111102_P01_BASE-BAND-TUBE-SIDE-RH_CAD (Autodesk Fusion 360 design; units mm, degrees)
description: BASE - BAND TUBE - SIDE - RH | Viền chân nhôm 100x40 - cạnh phải | part we make | rev P01 | DRAFT
part number: 111102
Autodesk Fusion 360 part; units mm, degrees
note: some values were not read from the file. Set by a fixed rule: the direction of a hole.
ref_plane "WorkPlane1" through (0, 0, 10) normal (0, 0, 1) x (1, 0, 0)
sketch "PLAN - SIDE RH - OUTLINE" plane through (0, 0, 10) normal (0, 0, 1) x (1, 0, 0)
  line L0 (1250, 850) -> (1250, -672)
  line L1 (1250, -672) -> (1210, -654.1721)
  line L2 (1210, -654.1721) -> (1210, 850)
  line L3 (1210, 850) -> (1250, 850)
  dimension "d169" = 1250
  dimension "d170" = 1210
  dimension "d171" = 672
  dimension "d172" = 654.1721
  dimension "d173" = 850
  constraint vertical L0
  constraint vertical L2
  constraint horizontal L3
  measures "d169" horizontal distance of origin L0.start
  measures "d170" horizontal distance of origin L1.end
  measures "d171" vertical distance of origin L0.end
  measures "d172" vertical distance of origin L1.end
  measures "d173" vertical distance of origin L2.end
extrude "EXTRUDE - SIDE RH - TUBE OUTSIDE" add sketch "PLAN - SIDE RH - OUTLINE" along normal blind 100
sketch "PLAN - SIDE RH - BORE" plane through (0, 0, 10) normal (0, 0, 1) x (1, 0, 0)
  line L0 (1211.5, -692) -> (1248.5, -692)
  line L1 (1248.5, -692) -> (1248.5, 870)
  line L2 (1248.5, 870) -> (1211.5, 870)
  line L3 (1211.5, 870) -> (1211.5, -692)
  dimension "d176" = 1248.5
  dimension "d177" = 1211.5
  dimension "d178" = 692
  dimension "d179" = 870
  constraint vertical L1
  constraint vertical L3
  constraint horizontal L0
  constraint horizontal L2
  measures "d176" horizontal distance of origin L0.end
  measures "d177" horizontal distance of origin L2.end
  measures "d178" vertical distance of origin L0.start
  measures "d179" vertical distance of origin L1.end
extrude "CUT - SIDE RH - BORE, WALL band_wall" cut sketch "PLAN - SIDE RH - BORE" along normal blind 97 from surface at 1.5
ref_plane "WorkPlane2" through (1210, 0, 0) normal (1, 0, 0) x (0, 1, 0)
sketch "HOLE POSITION - BACK KEY HOOK STUD BOLTS - BR (111211, D-129)" plane through (1210, 0, 0) normal (1, 0, 0) x (0, 0, -1)
  point P0 (-37.5, 830)
  dimension "d185" = 830
  dimension "d186" = 37.5
  measures "d185" vertical distance of origin P0
  measures "d186" horizontal distance of origin P0
hole "HOLE - BACK KEY HOOK STUD BOLTS - BR (111211, D-129)" at (1210, 830, 37.5) direction (1, 0, 0) diameter 7 depth 1.5 tip angle 118
pattern_linear "PATTERN - BACK KEY HOOK STUD BOLTS - BR (111211, D-129)" count 2 spacing 34 along (0, 0, 1) of "HOLE - BACK KEY HOOK STUD BOLTS - BR (111211, D-129)"
sketch "HOLE POSITION - BACK KEY FIXING - BR (111211, D-129)" plane through (0, 0, 10) normal (0, 0, 1) x (1, 0, 0)
  point P0 (1231, 823)
  dimension "d194" = 1231
  dimension "d195" = 823
  measures "d194" horizontal distance of origin P0
  measures "d195" vertical distance of origin P0
hole "HOLE - BACK KEY FIXING - BR (111211, D-129)" at (1231, 823, 10) direction (0, 0, 1) diameter 7 depth 1.5 tip angle 118
pattern_linear "PATTERN - BACK KEY FIXING - BR (111211, D-129)" count 2 spacing 14 along (0, 1, 0) of "HOLE - BACK KEY FIXING - BR (111211, D-129)"
ref_plane "WorkPlane3" through (0, 0, 110) normal (0, 0, 1) x (1, 0, 0)
sketch "HOLE POSITION - J-BASE-01 RIVNUT - R1" plane through (0, 0, 110) normal (0, 0, 1) x (1, 0, 0)
  point P0 (1224, -422.74)
  dimension "d205" = 1224
  dimension "d206" = 422.74
  measures "d205" horizontal distance of origin P0
  measures "d206" vertical distance of origin P0
hole "HOLE - J-BASE-01 RIVNUT - R1" at (1224, -422.74, 110) direction (0, 0, -1) diameter 9.53 depth 1.5 tip angle 118
pattern_linear "PATTERN - J-BASE-01 RIVNUT - R1" count 4 spacing 350.9133 along (0, 1, 0) of "HOLE - J-BASE-01 RIVNUT - R1"
sketch "HOLE POSITION - SPIGOT RIVNUT - R1" plane through (0, 0, 110) normal (0, 0, 1) x (1, 0, 0)
  point P0 (1224, -542.74)
  dimension "d214" = 1224
  dimension "d215" = 542.74
  measures "d214" horizontal distance of origin P0
  measures "d215" vertical distance of origin P0
hole "HOLE - SPIGOT RIVNUT - R1" at (1224, -542.74, 110) direction (0, 0, -1) diameter 9.53 depth 1.5 tip angle 118
pattern_linear "PATTERN - SPIGOT RIVNUT - R1" count 2 spacing 1292.74 along (0, 1, 0) of "HOLE - SPIGOT RIVNUT - R1"
sketch "HOLE POSITION - CORNER KEY FIXING - FR (111213)" plane through (0, 0, 10) normal (0, 0, 1) x (1, 0, 0)
  point P0 (1223, -643.5861)
  dimension "d223" = 1223
  dimension "d224" = 643.5861
  measures "d223" horizontal distance of origin P0
  measures "d224" vertical distance of origin P0
hole "HOLE - CORNER KEY FIXING - FR (111213)" at (1223, -643.5861, 10) direction (0, 0, 1) diameter 7 depth 1.5 tip angle 118
pattern_linear "PATTERN - CORNER KEY FIXING - FR (111213)" count 2 spacing 14 along (1, 0, 0) of "HOLE - CORNER KEY FIXING - FR (111213)"
sketch "HOLE POSITION - GLIDE KEY ACCESS - SIDE RH" plane through (0, 0, 110) normal (0, 0, 1) x (1, 0, 0)
  point P0 (1230, -597)
  dimension "d232" = 1230
  dimension "d233" = 597
  measures "d232" horizontal distance of origin P0
  measures "d233" vertical distance of origin P0
hole "HOLE - GLIDE KEY ACCESS - SIDE RH" at (1230, -597, 110) direction (0, 0, -1) diameter 8 depth 1.5 tip angle 118
pattern_linear "PATTERN - GLIDE KEY ACCESS - SIDE RH" count 2 spacing 1297 along (0, 1, 0) of "HOLE - GLIDE KEY ACCESS - SIDE RH"
sketch "HOLE POSITION - GLIDE NUT - SIDE RH" plane through (0, 0, 10) normal (0, 0, 1) x (1, 0, 0)
  point P0 (1230, -597)
  dimension "d241" = 1230
  dimension "d242" = 597
  measures "d241" horizontal distance of origin P0
  measures "d242" vertical distance of origin P0
hole "HOLE - GLIDE NUT - SIDE RH" at (1230, -597, 10) direction (0, 0, 1) diameter 13 depth 1.5 tip angle 118
pattern_linear "PATTERN - GLIDE NUT - SIDE RH" count 2 spacing 1297 along (0, 1, 0) of "HOLE - GLIDE NUT - SIDE RH"
equation "pod_w = 2500 mm" comment "SKELETON DECIDED: D-01; conventions s4 (X = +-1250)"
equation "pod_d = 1700 mm" comment "SKELETON DECIDED: D-01; conventions s4 (Y = +-850)"
equation "pod_h = 2400 mm" comment "SKELETON DECIDED: D-21 (room floor to roof skin top)"
equation "glide_h = 10 mm" comment "SKELETON ASSUMPTION: layout study inputs.py glide_h"
equation "band_h = 100 mm" comment "SKELETON SOURCE: layout study B1 list B-BAND 100x40; inputs.py base_h"
equation "band_t = 40 mm" comment "SKELETON SOURCE: layout study B1 list B-BAND 100x40"
equation "skin_t = 3 mm" comment "SKELETON DECIDED: ACP skin, walls and ceiling (D-16; PM ruling 2026-10-31 on outer_t)"
equation "bond_t = 3 mm" comment "SKELETON DECIDED: bond line between the ACP and the frame (PM ruling 2026-10-31 on outer_t)"
equation "frame_t = 40 mm" comment "SKELETON DECIDED: aluminium frame tube depth, walls and ceiling (PM ruling 2026-10-31 on outer_t)"
equation "outer_t = skin_t + bond_t + frame_t" comment "SKELETON DECIDED: PM ruling 2026-10-31: ACP 3 + bond line 3 + frame 40, walls and ceiling (was 43)"
equation "cav_gap = 4 mm" comment "SKELETON DECIDED: D-16, D-42: the gap between the outer panel and the lining cassette in the wall and ceiling stack"
equation "cass_t = 34 mm" comment "SKELETON SOURCE: layout study B1 final list L-CASS 34 (tray + 25 gap + felt 9)"
equation "stack_t = outer_t + cav_gap + cass_t" comment "SKELETON CALCULATION: D-16, D-42 stack, walls and ceiling: outer panel + cavity gap + cassette (PM ruling 2026-10-31 on outer_t)"
equation "wall_depth = 1495 mm" comment "SKELETON DECIDED: PM ruling pass C: side walls start at the decor back plate (Y -645), as v1 (1496)"
equation "lin_gap = 4 mm" comment "SKELETON ASSUMPTION: PM ruling pass C: gap above the upper side linings so they stay floating (= the 4 mm stack gap)"
equation "seam_gap = 2.26 mm" comment "SKELETON DECIDED: PM ruling 2026-10-31 (Mechanical Checker F-001, F-005): the Joints Engineer's 2.26 mm at all nine site seam types, set by a metal stop (1.5 stop washer + 0.76 rivnut head; joints register section 2.8)"
equation "mat_t = 0 mm" comment "SKELETON DECIDED: D-132 (PM ruling 2026-11-01): no floor, so no floor mat (was 3, D-72)"
equation "floor_t = 0 mm" comment "SKELETON DECIDED: D-132 (PM ruling 2026-11-01): no floor; people stand on the room floor (was 9)"
equation "thresh_h = 0 mm" comment "SKELETON DECIDED: D-132 (PM ruling 2026-11-01): no threshold, no step at the door; the door's drop seal closes on the room floor (was 13)"
equation "decor_d = 205 mm" comment "SKELETON SOURCE: v1 geometry per the PM ruling on D-39 (as v1; the drawings win): v1 decor-frame drawing frames 191 (left) and 197 (right) deep plus ACP and back plate = the v1 STEP shell, Y -850 to -645 = 205. D-39 and the B1 list say 230-235 (v1 BOM); see BUILD-RECORD-P02"
equation "dl_w = 278 mm" comment "SKELETON SOURCE: B1 list F-DL 278 (v1 BOM DL)"
equation "dr_w = 1016 mm" comment "SKELETON SOURCE: B1 list F-DR 1016 (v1 STEP solid 78)"
equation "dt_w = 1697 mm" comment "SKELETON SOURCE: B1 list F-DT 1697 (v1 BOM DT)"
equation "dt_h = 280 mm" comment "SKELETON SOURCE: B1 list F-DT 280"
equation "door_w = 1176 mm" comment "SKELETON DECIDED: D-46"
equation "door_h = 2011 mm" comment "SKELETON SOURCE: B1 list F-GLASS-DOOR 2011; v1 STEP solid 238"
equation "glass_t = 8.76 mm" comment "SKELETON DECIDED: D-46 (4+4 laminate)"
equation "glass_y = 699 mm" comment "SKELETON SOURCE: v1 STEP solid 238 centre Y = -699 (layout study data)"
equation "kick_d = 20 mm" comment "SKELETON ASSUMPTION: kick strip envelope depth (D-40 gives the height only)"
equation "kick_gap = 7 mm" comment "SKELETON SOURCE: FRONT door unit: 7 mm running gap under the kick strip for the drop seal (Mechanical Checker F-002 on P03); since D-132 the PM puts the kick strip's bottom on the band's bottom line, glide_h, so the skeleton's kick envelope no longer uses it"
equation "fr_dz = 17 mm" comment "SKELETON CALCULATION: v1 front top 2417 (v2 frame) - pod_h 2400"
equation "door_xl = 289 mm" comment "SKELETON SOURCE: V1-FRONT-FACETS: door left edge X -961 = -1250 + 289"
equation "door_xbr = 1464 mm" comment "SKELETON SOURCE: V1-FRONT-FACETS: door bottom-right X 214"
equation "door_xtr = 1182 mm" comment "SKELETON SOURCE: V1-FRONT-FACETS: door top-right X -68"
equation "door_zb = 122 mm - fr_dz" comment "SKELETON SOURCE: V1-FRONT-FACETS: door bottom Z 122"
equation "door_zt = 2133 mm - fr_dz" comment "SKELETON SOURCE: V1-FRONT-FACETS: door top Z 2133"
equation "glass_gap = 4 mm" comment "SKELETON DECIDED: PM ruling 2026-10-31 on Mechanical Checker F-014: the fixed glass's free edge runs parallel to the door's slanted edge, 4.0 mm away (FRONT's glass in PR #28 is the reference)"
equation "fix_xbr = 302 mm" comment "SKELETON SOURCE: V1-FRONT-FACETS: fixed glass bottom-right X 948 = 1250 - 302"
equation "fix_xk = 501 mm" comment "SKELETON SOURCE: V1-FRONT-FACETS: fixed glass knee X 749 = 1250 - 501"
equation "fix_zk = 1538 mm - fr_dz" comment "SKELETON SOURCE: V1-FRONT-FACETS: fixed glass knee Z 1538"
equation "fix_xtr = 1480 mm" comment "SKELETON SOURCE: V1-FRONT-FACETS: fixed glass top-right X 230 = -1250 + 1480"
equation "fix_zb = 119 mm - fr_dz" comment "SKELETON SOURCE: V1-FRONT-FACETS: fixed glass bottom Z 119"
equation "fix_zt = 2136 mm - fr_dz" comment "SKELETON SOURCE: V1-FRONT-FACETS: fixed glass top Z 2136"
equation "dt_zb = 2137 mm - fr_dz" comment "SKELETON SOURCE: V1-FRONT-FACETS: DT and DR edge above the glass Z 2137"
equation "ch_zlo = 2217 mm - fr_dz" comment "SKELETON SOURCE: V1-FRONT-FACETS: top chamfer front edge Z 2217 at Y -848"
equation "ch_yb = 672 mm" comment "SKELETON SOURCE: V1-FRONT-FACETS: top chamfer back edge Y -672"
equation "dl_x2 = 92 mm" comment "SKELETON SOURCE: V1-FRONT-FACETS: DL facet knee X -1158 = -1250 + 92"
equation "dl_y2 = 752 mm" comment "SKELETON SOURCE: V1-FRONT-FACETS: DL facet knee Y -752"
equation "dl_x3 = 271 mm" comment "SKELETON SOURCE: V1-FRONT-FACETS: DL front corner X -979"
equation "dl_y3 = 844 mm" comment "SKELETON SOURCE: V1-FRONT-FACETS: DL front corner Y -844"
equation "dl_y1 = 670 mm" comment "SKELETON SOURCE: V1-FRONT-FACETS: DL outer facet start Y -670"
equation "dl_zo = 2414 mm - fr_dz" comment "SKELETON SOURCE: V1-FRONT-FACETS: DL top at the outer corner Z 2414"
equation "dt_x2 = 281 mm" comment "SKELETON SOURCE: V1-FRONT-FACETS: DT lower facet left X -969 = -1250 + 281"
equation "dt_y2 = 767 mm" comment "SKELETON SOURCE: V1-FRONT-FACETS: DT lower facet left Y -767"
equation "dt_y3 = 753 mm" comment "SKELETON SOURCE: V1-FRONT-FACETS: DT lower facet outer Y -753 at X -1154"
equation "dr_xc = 198 mm" comment "SKELETON SOURCE: V1-FRONT-FACETS: DR corner facet front X 1052 = 1250 - 198"
equation "dt_xr = 1699 mm" comment "SKELETON SOURCE: V1-FRONT-FACETS: DT/DR joint at the top, X 449 = -1250 + 1699 (PM ruling pass C)"
equation "dr_yc = 672 mm" comment "SKELETON SOURCE: V1-FRONT-FACETS: DR corner facet back Y -672"
equation "fix_xbl = door_xbr + ( door_zb - fix_zb ) * ( door_xbr - door_xtr ) / ( door_zt - door_zb ) + glass_gap * sqrt(( door_xbr - door_xtr ) * ( door_xbr - door_xtr ) + ( door_zt - door_zb ) * ( door_zt - door_zb )) / ( door_zt - door_zb )" comment "SKELETON CALCULATION: F-014: fixed glass bottom-left, on the line glass_gap from the door's slanted edge (was v1's 1468)"
equation "fix_xtl = door_xbr + ( door_zb - fix_zt ) * ( door_xbr - door_xtr ) / ( door_zt - door_zb ) + glass_gap * sqrt(( door_xbr - door_xtr ) * ( door_xbr - door_xtr ) + ( door_zt - door_zb ) * ( door_zt - door_zb )) / ( door_zt - door_zb )" comment "SKELETON CALCULATION: F-014: fixed glass top-left, on the same line (was v1's 1184)"
equation "floor_top = mat_t + floor_t" comment "SKELETON CALCULATION: the floor top: Z 0, the room floor itself (D-132: no floor; was Z 12)"
equation "wall_z0 = glide_h + band_h" comment "SKELETON CALCULATION: base band top: glides + band"
equation "panel_z0 = wall_z0 + seam_gap" comment "SKELETON CALCULATION: walls stand one seam_gap above the band top (joints register 2.8, IF-01)"
equation "wall_h = pod_h - wall_z0" comment "SKELETON CALCULATION: 2290 = layout study v2_model wall_h"
equation "side_h = ( wall_h - 2 * seam_gap ) / 2" comment "SKELETON CALCULATION: D-23: 2 sheets per side wall; the gap on the band and the horizontal seam (joints register 2.8)"
equation "side_l = wall_depth - seam_gap" comment "SKELETON CALCULATION: side panel length along Y: the seam_gap at the decor's back plate (joints register 2.8, IF-07)"
equation "back_oh = pod_h - outer_t - seam_gap - panel_z0" comment "SKELETON CALCULATION: PM ruling 2026-10-31 (pass D, F-004): the back outer frames run up to the ceiling frame (pod_h - outer_t), less the seam_gap under it, closing the slot at the back top edge"
equation "back_ph = ( back_oh - seam_gap ) / 2" comment "SKELETON CALCULATION: D-23: 4 sheets on the back, two equal rows with one seam_gap between them (joints register 2.8); the lower back linings match the lower row, as on the side walls"
equation "half_pw = ( pod_w - 2 * outer_t - 3 * seam_gap ) / 2" comment "SKELETON CALCULATION: SKIN width of each back and ceiling panel: two skins and three seam_gap seams between the side frames (F-001, joints register 2.8)"
equation "close_gap = 5.5 mm" comment "SKELETON DECIDED: PM ruling 2026-10-31 (joints register, F-011/F-012): frame gap at the closing seams B1-B2, B3-B4 and C1-C2, which have no hard stop (slotted holes, thicker gasket)"
equation "half_fw = ( pod_w - 2 * outer_t - 2 * seam_gap - close_gap ) / 2" comment "SKELETON CALCULATION: FRAME width of each back and ceiling panel: the skins overhang their frames by half_pw - half_fw at the closing seam (PM ruling 2026-10-31)"
equation "inner_w = pod_w - 2 * stack_t" comment "SKELETON CALCULATION: inside width between the side linings"
equation "bolt_edge_inset = 220 mm" comment "SKELETON DECIDED: PM ruling 2026-10-31: on every bolted edge the end bolts sit this far in from each panel end (the FRAME end, where the bolts go), the rest evenly spaced"
equation "spigot_inset = 100 mm" comment "SKELETON DECIDED: PM ruling 2026-10-31: locating spigots this far in from each panel end (round hole at one end, slot at the other)"
equation "base_bolt_edge = bolt_edge_inset" comment "SKELETON DECIDED: J-BASE-01 wall to band: the edge rule (kept by this name for parts already linked)"
equation "n_base_bolt = 4" comment "SKELETON DECIDED: PM ruling 2026-10-31, J-BASE-01: bolts per panel along the band, evenly spaced"
equation "base_spigot_inset = spigot_inset" comment "SKELETON DECIDED: J-BASE-01: the spigot rule (kept by this name for parts already linked)"
equation "base_side_y0 = pod_d / 2 - wall_depth + seam_gap" comment "SKELETON CALCULATION: J-BASE-01: side bolt lines start at the side panel's front end (first bolt base_bolt_edge further on)"
equation "side_base_pitch = ( side_l - 2 * base_bolt_edge ) / ( n_base_bolt - 1 )" comment "SKELETON CALCULATION: J-BASE-01 bolt pitch along a side panel"
equation "base_back_x0 = pod_w / 2 - outer_t - seam_gap" comment "SKELETON CALCULATION: J-BASE-01: back bolt lines start at each back FRAME's outer end, X -/+ this (first bolt base_bolt_edge further in)"
equation "back_base_pitch = ( half_fw - 2 * base_bolt_edge ) / ( n_base_bolt - 1 )" comment "SKELETON DECIDED: PM ruling 2026-10-31 (Reviewer 5 P2 on #58): J-BASE-01 pitch along a back panel, measured on the FRAME (half_fw), where the bolts go; 'panel end' means the frame end"
equation "ceil_bolt_z = pod_h - outer_t + frame_t / 2" comment "SKELETON DECIDED: PM ruling 2026-10-31, J-CEIL-01 wall to ceiling: the bolt line on the ceiling frame's centre (Z 2374)"
equation "n_ceil_side_bolt = 4" comment "SKELETON DECIDED: PM ruling 2026-10-31, J-CEIL-01: bolts along each side wall top"
equation "n_ceil_back_bolt = 4" comment "SKELETON DECIDED: PM ruling 2026-10-31, J-CEIL-01: bolts along each back panel top, like the base (pitch about 253, every edge 350 or less; joints register: 82 bolts in all)"
equation "ceil_side_y0 = pod_d / 2 - wall_depth" comment "SKELETON DECIDED: PM ruling 2026-10-31 (joints register): J-CEIL-01 side bolt lines start at Y -645, measured along the ceiling (first bolt bolt_edge_inset further on)"
equation "ceil_side_pitch = ( wall_depth - 2 * bolt_edge_inset ) / ( n_ceil_side_bolt - 1 )" comment "SKELETON DECIDED: PM ruling 2026-10-31 (joints register): J-CEIL-01 pitch along a side wall top, over the ceiling's length (was over the side panel's)"
equation "ceil_back_x0 = pod_w / 2 - outer_t - seam_gap" comment "SKELETON DECIDED: PM ruling 2026-10-31 (joints register): J-CEIL-01 back bolt lines start at each back frame's outer end, X -/+ this"
equation "ceil_back_pitch = ( half_fw - 2 * bolt_edge_inset ) / ( n_ceil_back_bolt - 1 )" comment "SKELETON DECIDED: PM ruling 2026-10-31 (joints register): J-CEIL-01 pitch along a back panel top, on the frame (half_fw)"
equation "band_wall = 1.5 mm" comment "BASE CONFIRMED: PM ruling 2026-10-31 (BASE group): 100 x 40 x 1.5 base band (was 2.0), with a doubler at each glide; rivnut coupon in 1.5 mm added to the rivnut test"
equation "band_finish = 'Black anodised, matte, 20 um (class AA20, EN ISO 7599)'" comment "BASE CONFIRMED: PM ruling 2026-10-31 (BASE group): every base band piece and the door's kick strip"
equation "cap_t = 2 mm" comment "BASE SOURCE: the side band's back-end cap 118003: flat, inside the tube's end and flush with the back face Y = pod_d/2, no deeper than 2, as the back corner key sits 2.5 from the end (D-129, joints register J-BASE-02); product HOLD"
equation "jb_x = outer_t - frame_t / 2" comment "BASE CALCULATION: J-BASE-01 bolt line: centre of the wall's bottom tube, 26 in from the pod's outer face (joints register 3.4: X -1224, Y +824)"
equation "rn_hole = 9.53 mm" comment "BASE SOURCE: Sherex CAH2-610-4.2 M6 rivet nut, steel, zinc plated (joints register H-03, D-131): hole 9.53 +0.10/0, as the aluminium part's it replaced (unverified for the steel part, HOLD-04)"
equation "rn_flange = 12.96 mm" comment "BASE SOURCE: CAH2-610-4.2 head diameter 12.96 (joints register H-03)"
equation "rn_inst = 10.16 mm" comment "BASE SOURCE: CAH2-610-4.2 installed length, at most 10.16 (joints register H-03, maker data)"
equation "rn_head_t = 0.76 mm" comment "BASE SOURCE: CAH2-610-4.2 head height 0.76 +-0.08 (joints register H-03, maker data)"
equation "sw_hole = 10.5 mm" comment "BASE SOURCE: stop washer bore (joints register H-08, PROPOSED)"
equation "sw_d = 20 mm" comment "BASE SOURCE: stop washer outside diameter (joints register H-08, PROPOSED)"
equation "sw_t = 1.5 mm" comment "BASE SOURCE: stop washer, under each bolt rivnut's head: washer 1.5 + head 0.76 = seam_gap 2.26, so the walls stand at panel_z0 (D-64)"
equation "jb_n = n_base_bolt" comment "BASE CONFIRMED: skeleton n_base_bolt (D-75, joints register R-J13): 4 bolts per wall panel on the band"
equation "jb_e = base_bolt_edge" comment "BASE CONFIRMED: skeleton base_bolt_edge (D-75, R-J13): end bolts 220 in from each panel FRAME end, evenly spaced (PM ruling: measured on the frame, not the skin)"
equation "sp_e = base_spigot_inset" comment "BASE CONFIRMED: skeleton base_spigot_inset (D-75, R-J13): spigots 100 in from each panel frame end"
equation "sp_dia = 8 mm" comment "BASE SOURCE: locating spigot, stainless, M6 thread (joints register H-05, PROPOSED sizes)"
equation "sp_proud = 8 mm" comment "BASE SOURCE: spigot stands 8 proud of the band top (joints register H-05, PROPOSED)"
equation "sp_ch = 1 mm" comment "BASE ASSUMPTION: lead-in chamfer on the spigot top"
equation "sp_stud = 8 mm" comment "BASE ASSUMPTION: spigot's M6 stud into its rivnut, with threadlocker"
equation "gl_n_side = 2" comment "BASE CALCULATION: glides per side band: span about 1.3 m, sag under 0.5 mm (see feature rationale)"
equation "gl_n_back = 3" comment "BASE CALCULATION: glides on the back band: 2 spans of 1060 (see feature rationale)"
equation "gl_e_f = 75 mm" comment "BASE CALCULATION: front glide of a side band, behind the band's outer front corner (Y = -dl_y1): its doubler (26 each way) stays 15 behind the front corner key's back face (Y -636.03) and out of the keyed end's last 30 mm, which the joints register asks BASE to keep clear (PR #99, J-BASE-02)"
equation "gl_e_b = 150 mm" comment "BASE ASSUMPTION: back glide of a side band from the back face"
equation "gl_e_bb = 150 mm" comment "BASE ASSUMPTION: end glides of the back band from its ends"
equation "gl_key_hole = 8 mm" comment "BASE ASSUMPTION: hole in the band top for the 5 mm hex key that turns the glide (5.77 across corners, so 1.1 clear each side; levelled before the walls go on). On the band's centre line it spans 16 to 24 from the outer face, inboard of the PORON strip that runs beside the washer line on its outer side (8 to 16, joints register FR-11)"
equation "gl_dx = 0 mm" comment "BASE CONFIRMED: PM ruling 2026-10-31 (BASE group): the doubler's hole centred across its 36 mm width, so the glide stands on the band's centre line"
equation "gl_nut_hole = 13 mm" comment "BASE ASSUMPTION: hole in the band bottom for an M10 rivet nut that carries the glide; nut product HOLD"
equation "gl_pad = 36 mm" comment "BASE ASSUMPTION: glide pad diameter (envelope, HOLD); stays inside the band's 40 mm width"
equation "gl_stem = 10 mm" comment "BASE ASSUMPTION: glide stem M10 (envelope, HOLD)"
equation "gl_nut_t = 2 mm" comment "BASE ASSUMPTION: M10 rivet nut head under the band, between the band and the glide pad (HOLD)"
equation "gl_min = 8.5 mm" comment "BASE SOURCE: lowest glide setting: the corner keys' button heads hang 3.3 under the band and nothing may come within 5 of the floor (PM ruling on F-018; joints register PR #99 via the Lead, 2026-11-01)"
equation "gl_base_min = gl_min - gl_nut_t" comment "BASE CALCULATION: the glide's base must stand this tall (6.5), so that screwed fully home against the M10 rivnut's head it holds the band at gl_min: a hard stop (glide spec, HOLD)"
equation "gd_l = 54 mm" comment "BASE CONFIRMED: PM ruling 2026-10-31 (BASE group, the Checker's edge rule): glide doubler at least 52 long, so its ends are 2 hole diameters (26) from the hole; 54 gives 27, clear of that line"
equation "gd_w = band_t - 2 * band_wall - 1 mm" comment "BASE CALCULATION: glide doubler width: the band's bore less 1 mm, so it bears on the bottom face right next to both side walls"
equation "gd_t = 5 mm" comment "BASE CONFIRMED: load block (glide doubler) 5 mm EN AW-6082 T6 (PM ruling 2026-11-01 on the D-132 PR): about 43 MPa at the worst glide's 0.75 kN and 97 at 1.7 kN, against about 250 (plate spanning the bore, edges free to turn; feature rationale); clamped with the 1.5 mm bottom face by the glide's M10 rivnut (grip 6.5)"
equation "ck_x = 30 mm" comment "BASE SOURCE: corner key length into its carrier: 30, so the carrier's Ø7.0 fixing holes keep 2 diameters from its cut end (joints register #127)"
equation "ck_y = 35 mm" comment "BASE SOURCE: back corner key width across the band (J-BASE-02)"
equation "ck_z = 75 mm" comment "BASE SOURCE: back corner key height, standing on the band's bottom wall: 75 (the Joints Engineer, via the Lead 2026-11-01)"
equation "ck_e = 10.5 mm" comment "BASE SOURCE: key fixing holes 10.5 from its back face (inside the band) and 7.0 either side of its centre line, so 10.5 from its side faces (joints register #127, J-BASE-02)"
equation "ck_fix_hole = 7 mm" comment "BASE SOURCE: the keys' fixing screw holes in the carrier's bottom wall, Ø7.0 (J-BASE-02); the side bands carry the back keys since D-129"
equation "ck_tap = 5 mm" comment "BASE SOURCE: M6 tap drill in the key (J-BASE-02)"
equation "ck_thr_b = 15 mm" comment "BASE CONFIRMED: M6 thread in the key's bottom at least 15 deep: the M6 x 16 fixing bolt reaches 12.9 (PM ruling 2026-11-01 on F-017, joints group)"
equation "ck_tap_d = 18 mm" comment "BASE SOURCE: tap drill Ø5.0, 18 deep, under the 15 of full thread (joints register PR #99, J-BASE-02)"
equation "st_z1 = 26 mm" comment "BASE SOURCE: lower hook stud above the key's bottom: pod Z 37.5 with glide_h 10 and band_wall 1.5, so the keyhole's entry below it clears the tube's bottom corner (the Joints Engineer, via the Lead 2026-11-01)"
equation "st_z2 = 60 mm" comment "BASE SOURCE: upper hook stud above the key's bottom: pod Z 71.5 (the Joints Engineer, via the Lead 2026-11-01)"
equation "st_gap = 1.8 mm" comment "BASE SOURCE: hook stud head's underside off the face the next piece hooks onto: its 1.5 wall or plate + 0.3 clearance (J-BASE-02)"
equation "kh_entry = 12 mm" comment "BASE SOURCE: keyhole entry in the front joints' 1.5 end caps, Ø12 (J-BASE-02)"
equation "kh_slot = 6.5 mm" comment "BASE SOURCE: keyhole and slot width, 6.5, locates each joint across the band to ±0.25 (Ø5.97 shank, J-BASE-02)"
equation "kh_drop = 10 mm" comment "BASE SOURCE: entry centre 10 BELOW the stud's final spot, the slot running 10 up to it: a front piece goes on 10 high, then drops onto the studs (the Joints Engineer's fix, via the Lead 2026-11-01)"
equation "st_hole = 7 mm" comment "BASE SOURCE: the hook stud bolts' holes through the side band's inner wall at the back corners, Ø7.0 (D-129, J-BASE-02, FR-15)"
equation "bs_mouth_w = 12 mm" comment "BASE SOURCE: each back band end cap's slot: 12 wide at the cap's bottom edge, its mouth (D-129, J-BASE-02, FR-15)"
equation "bs_mouth_h = 6 mm" comment "BASE SOURCE: the mouth narrows to the 6.5 slot over the cap's bottom 6 (D-129, FR-15)"
equation "bs_end = 2 mm" comment "BASE SOURCE: the slot's closed end centred 2 above the upper stud (Z 73.5): the band rests on its glides, never on the studs (D-129, FR-15)"
equation "hn_w = 12 mm" comment "BASE SOURCE: head notch in the back band's bottom wall at each end, 12 wide: the Ø10 head and 1 each side (D-129, FR-15)"
equation "hn_d = 9 mm" comment "BASE SOURCE: head notch 9 deep from the band's end: the head's far face is 1.8 + 6 = 7.8 from the side band's face (D-129, FR-15)"
equation "cap_bevel = 1 mm" comment "BASE SOURCE: 1 x 45 deg bevel on each back band end cap's bottom edge, side-band side, so it slips under the heads (D-129, FR-15)"
equation "gl_max = 18.5 mm" comment "BASE ASSUMPTION: the band's bottom at the glides' highest setting: 10 mm of travel above the lowest, gl_min (HOLD with the glide product)"
equation "seal_press = 3 mm" comment "BASE ASSUMPTION: the lip's least press on the room floor, at the glides' highest setting"
equation "seal_reach = gl_max + seal_press" comment "BASE CALCULATION: the lip reaches this far below the band's bottom (21.5), so it touches the room floor across the glides' range (D-132)"
equation "seal_leg = 15 mm" comment "BASE ASSUMPTION: the lip's leg, bonded to the band's inner face from its bottom edge up (adhesive HOLD)"
equation "seal_t = 10 mm" comment "BASE ASSUMPTION: the lip's room into the pod from the band's inner face, modelled as an envelope from the room floor to seal_leg above the band's bottom"
equation "mesh_front = 105 mm" comment "BASE CONFIRMED: DR intake mesh: 105 on the front and 266 on the facet (D-62)"
equation "mesh_t = 2 mm" comment "BASE ASSUMPTION: intake mesh thickness (expanded aluminium, 80 % free, black; product HOLD)"
equation "rail_w = 20 mm" comment "BASE ASSUMPTION: DR support rail flange under DR's bottom edge"
equation "rail_h = 30 mm" comment "BASE ASSUMPTION: DR support rail leg"
equation "rail_t = 2 mm" comment "BASE ASSUMPTION: DR support rail thickness (aluminium angle)"
equation "rail_set = 20 mm" comment "BASE ASSUMPTION: rail set back behind the mesh, so it blocks none of the mesh face"
equation "cp_t = 2 mm" comment "BASE ASSUMPTION: closing plate between the intake space and the pod (D-62)"
equation "fr_stub = 32 mm" comment "BASE CONFIRMED: the intake's band stub left of the mesh, carrying the inline key 111211 (30 long since the Joints Engineer's change of 2026-11-01) behind no mesh, with 2 to spare (PM ruling 2026-11-01: the joint moves left of the mesh)"
equation "x_fr_joint = pod_w / 2 - dr_xc - mesh_front - fr_stub" comment "BASE CONFIRMED: the FR1 / intake joint, X 915 (PM rulings 2026-11-01: X 920 for the 25 mm key, then X 915 for the 30 mm key): FR1 runs X 218.5 to here; the intake from here, its mesh from X 947"
equation "ch_w = 15 mm" comment "BASE SOURCE: FRONT: the glass's bottom U-channel, Bohle 15 x 15 x 1.5, Y -706.5 to -691.5 (centred on glass_y)"
equation "ch_h = 15 mm" comment "BASE SOURCE: FRONT: channel underside Z 95, top Z 110 (the band top, the glass's visible bottom line)"
equation "sl_t = 2 mm" comment "BASE ASSUMPTION: sill sheet: aluminium 2 mm, bent, black anodised AA20 (D-67 look)"
equation "sl_flange = 40 mm" comment "BASE ASSUMPTION: sill's fixing flange down FR1's inner face (blind rivets, HOLD)"
equation "sl_x1 = 965 mm" comment "BASE SOURCE: FRONT: the channel's underside runs to X 964.1, so the sill reaches X 965"
equation "ch_screw_x1 = 269.4 mm" comment "BASE SOURCE: FRONT's channel holes (F-368004-02): the first at X 269.4"
equation "ch_screw_p = 214.9 mm" comment "BASE SOURCE: FRONT's pitch for the first 3 channel holes: X 269.4, 484.3, 699.2"
equation "ch_screw_x4 = 905 mm" comment "BASE CONFIRMED: the last channel screw at X 905: on FR1's sill seat, 2 hole diameters from FR1's end at x_fr_joint (joints register J-FRONT-04, the Lead 2026-11-01: X 905 or less; FRONT's 914.1 moves)"
equation "ch_rn_hole = 5 mm" comment "BASE ASSUMPTION: hole for the flush-head M3 rivnut in the sill seat (product with the Joints Engineer, HOLD)"
equation "d167 = glide_h"
equation "d169 = abs(pod_w / 2)"
equation "d170 = abs(pod_w / 2 - band_t)"
equation "d171 = abs(-dr_yc)"
equation "d172 = abs(( -dr_yc + band_t * ( sqrt(dr_xc ^ 2 + ( pod_d / 2 - dr_yc ) ^ 2) - ( pod_d / 2 - dr_yc ) ) / dr_xc ))"
equation "d173 = abs(pod_d / 2)"
equation "d174 = band_h"
equation "d176 = abs(pod_w / 2 - band_wall)"
equation "d177 = abs(pod_w / 2 - band_t + band_wall)"
equation "d178 = abs(-dr_yc - 20 mm)"
equation "d179 = abs(pod_d / 2 + 20 mm)"
equation "d180 = band_wall"
equation "d181 = band_h - 2 * band_wall"
equation "d183 = ( pod_w / 2 - band_t )"
equation "d185 = abs(pod_d / 2 - band_t / 2)"
equation "d186 = abs(glide_h + band_wall + st_z1)"
equation "d187 = band_wall"
equation "d188 = st_hole"
equation "d192 = st_z2 - st_z1"
equation "d194 = abs(( pod_w / 2 - band_t + band_wall + ck_x - ck_e ))"
equation "d195 = abs(pod_d / 2 - band_t / 2 - ( ck_y / 2 - ck_e ))"
equation "d196 = band_wall"
equation "d197 = ck_fix_hole"
equation "d201 = ck_y - 2 * ck_e"
equation "d203 = wall_z0"
equation "d205 = abs(pod_w / 2 - jb_x)"
equation "d206 = abs(base_side_y0 + jb_e)"
equation "d207 = band_wall"
equation "d208 = rn_hole"
equation "d210 = jb_n"
equation "d212 = side_l - 2 * jb_e"
equation "d214 = abs(pod_w / 2 - jb_x)"
equation "d215 = abs(base_side_y0 + sp_e)"
equation "d216 = band_wall"
equation "d217 = rn_hole"
equation "d221 = side_l - 2 * sp_e"
equation "d223 = abs(pod_w / 2 - band_t / 2 - ( ck_y / 2 - ck_e ))"
equation "d224 = abs(( -dr_yc + ( -dr_yc + band_t * ( sqrt(dr_xc ^ 2 + ( pod_d / 2 - dr_yc ) ^ 2) - ( pod_d / 2 - dr_yc ) ) / dr_xc ) ) / 2 + ck_x - ck_e)"
equation "d225 = band_wall"
equation "d226 = ck_fix_hole"
equation "d230 = ck_y - 2 * ck_e"
equation "d232 = abs(pod_w / 2 - band_t / 2 - gl_dx)"
equation "d233 = abs(-dr_yc + gl_e_f)"
equation "d234 = band_wall"
equation "d235 = gl_key_hole"
equation "d237 = gl_n_side"
equation "d239 = pod_d / 2 - gl_e_b + dr_yc - gl_e_f"
equation "d241 = abs(pod_w / 2 - band_t / 2 - gl_dx)"
equation "d242 = abs(-dr_yc + gl_e_f)"
equation "d243 = band_wall"
equation "d244 = gl_nut_hole"
equation "d246 = gl_n_side"
equation "d248 = pod_d / 2 - gl_e_b + dr_yc - gl_e_f"
named bodies: "BASE - BAND TUBE - SIDE - RH - TUBE"
